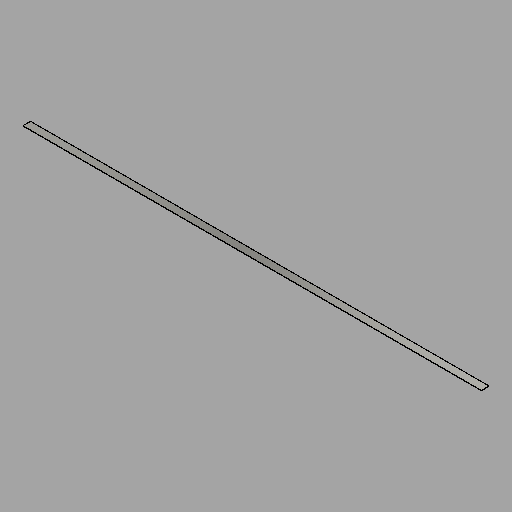
# Autodesk Inventor part: Busbar_Mid_Center
Saved by Autodesk Inventor 2026.2 (Build 302298000, 298)
## iProperties
Created: 2026-11-08
Part Number: Busbar_Mid_Center
Material: Generic
Document SubType Name: Modeling
Designer: Jacob
Density: 1 g/cm^3
Appearance: Default
Author: Jacob
Cu_Thickness: 0.310 mm
Coating_Thickness: 0.020 mm
Total_Thickness: 0.350 mm
Busbar_Width: 6.000 mm
Cu_Width: 5.960 mm
Busbar_Length: 358.600 mm
Autodesk Inventor part; units mm, degrees
ref_plane "YZ Plane" through (0, 0, 0) normal (1, 0, 0) x (0, 1, 0)
ref_plane "XZ Plane" through (0, 0, 0) normal (0, 1, 0) x (-1, 0, 0)
ref_plane "XY Plane" through (0, 0, 0) normal (0, 0, 1) x (1, 0, 0)
sketch "Sketch1" plane through (0, 0, 0) normal (1, 0, 0) x (0, 1, 0)
  line L0 (0.02, -2.98) -> (0.33, -2.98)
  line L1 (0.33, -2.98) -> (0.33, 2.98)
  line L2 (0.33, 2.98) -> (0.02, 2.98)
  line L3 (0.02, 2.98) -> (0.02, -2.98)
  line L4 (0.02, -2.98) -> (0.33, 2.98) construction
  line L5 (0.33, -2.98) -> (0.02, 2.98) construction
  point P0 (0.175, 0)
  constraints: 12 end point, 2 midpoint, 2 parallel, 1 horizontal, 1 perpendicular
extrude "Copper_Core_Extrude" add sketch "Sketch1" along normal mid plane 358.6
sketch "Sketch2" plane through (0, 0, 0) normal (1, 0, 0) x (0, 1, 0)
  line L0 (0.02, -2.98) -> (0.33, -2.98)
  line L1 (0.33, -2.98) -> (0.33, 2.98)
  line L2 (0.33, 2.98) -> (0.02, 2.98)
  line L3 (0.02, 2.98) -> (0.02, -2.98)
  line L4 (0.02, -2.98) -> (0.33, 2.98) construction
  line L5 (0.33, -2.98) -> (0.02, 2.98) construction
  line L6 (0, -3) -> (0.35, -3)
  line L7 (0.35, -3) -> (0.35, 3)
  line L8 (0.35, 3) -> (0, 3)
  line L9 (0, 3) -> (0, -3)
  line L10 (0, -3) -> (0.35, 3) construction
  line L11 (0.35, -3) -> (0, 3) construction
  point P0 (0.175, 0)
  point P1 (0.175, 0)
  constraints: 24 end point, 4 midpoint, 4 parallel, 2 horizontal, 2 perpendicular
extrude "SnPb_Coating_Extrude" add sketch "Sketch2" along normal mid plane 358.6 separate body contours L3 L2 L1 L0 | L9 L8 L7 L6
equation "\"d0\" = Busbar_Length"
equation "\"d2\" = Busbar_Length"
equation "\"Cu_Thickness\" = 0.31"
equation "\"Coating_Thickness\" = 0.02"
equation "\"Total_Thickness\" = Cu_Thickness + 2 * Coating_Thickness"
equation "\"Busbar_Width\" = 6"
equation "\"Cu_Width\" = Busbar_Width - 2 * Coating_Thickness"
equation "\"Busbar_Length\" = 358.6"
